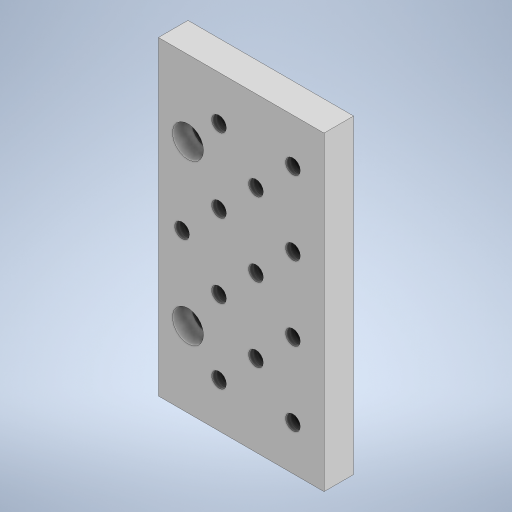
# Autodesk Inventor part: Kinetix_Adapter_V1
Saved by Autodesk Inventor 2023 (Build 270158000, 158)
## iProperties
Created: 2023-07-07
Part Number: Kinetix_Adapter_V1
Material: Generic
Document SubType Name: Modeling
Designer: B0067-WS-2
Density: 1 g/cm^3
Appearance: Default
Author: B0067-WS-2
Autodesk Inventor part; units mm, degrees
ref_plane "YZ Plane" through (0, 0, 0) normal (1, 0, 0) x (0, 1, 0)
ref_plane "XZ Plane" through (0, 0, 0) normal (0, 1, 0) x (-1, 0, 0)
ref_plane "XY Plane" through (0, 0, 0) normal (0, 0, 1) x (1, 0, 0)
sketch "Sketch1" plane through (0, 0, 0) normal (0, 0, 1) x (1, 0, 0)
  line L0 (-19.2, 0) -> (59.2, 0) construction
  line L1 (0, -73.5) -> (0, 73.5) construction
  line L2 (-8, 52.5) -> (48, 52.5)
  line L3 (48, 52.5) -> (48, -52.5)
  line L4 (48, -52.5) -> (-8, -52.5)
  line L5 (-8, -52.5) -> (-8, 52.5)
  point P0 (0, 0)
  dimension "d0" = 105
  dimension "d1" = 56
  dimension "d2" = 8
  constraints: 8 end point, 2 parallel, 1 horizontal, 1 perpendicular, 1 other
  measures "d0" distance between parallel lines of L4 L2
  measures "d1" distance of L2.start L2.end
  measures "d2" distance between parallel lines of L5 L1
extrude "Extrusion1" add sketch "Sketch1" along normal blind 10
sketch "Sketch2" plane through (0, 0, 10) normal (0, 0, 1) x (1, 0, 0)
  line L0 (-22, 0) -> (62, 0) construction
  line L1 (0, 73.5) -> (0, -73.5) construction
  line L2 (-8, -52.5) -> (48, -52.5) construction
  line L3 (48, -52.5) -> (48, 52.5) construction
  line L4 (48, 52.5) -> (-8, 52.5) construction
  line L5 (-8, 52.5) -> (-8, -52.5) construction
  point P0 (0, 0)
  point P1 (2, 27)
  point P2 (2, -27)
  dimension "d5" = 54
  dimension "d6" = 10
  constraints: 1 symmetric about line
  measures "d5" distance of point (2, -27) point (2, 27)
  measures "d6" distance from line of L5 point (2, 27)
hole "Hole1" at (2, 27, 10) at (2, -27, 10) direction (0, 0, -1) diameter 6.5 end through all counterbore diameter 10.5 counterbore depth 6.5
sketch "Sketch3" plane through (0, 0, 10) normal (0, 0, 1) x (1, 0, 0)
  circle A0 centre (2, 27) radius 5.25 construction
  circle A1 centre (2, -27) radius 5.25 construction
  line L0 (-8, -52.5) -> (48, -52.5) construction
  line L1 (48, -52.5) -> (48, 52.5) construction
  line L2 (48, 52.5) -> (-8, 52.5) construction
  line L3 (-8, 52.5) -> (-8, -52.5) construction
  line L4 (-19.2, 0) -> (59.2, 0) construction
  line L5 (48, 52.5) -> (-8, 52.5) construction
  line L6 (25, 52.5) -> (25, -52.5) construction
  line L7 (-8, -52.5) -> (48, -52.5) construction
  line L8 (12.5, 52.5) -> (12.5, -52.5) construction
  line L9 (37.5, 52.5) -> (37.5, -52.5) construction
  point P0 (0, 0)
  point P1 (0, 0)
  point P2 (25, 0)
  point P3 (25, 25)
  point P4 (25, -25)
  point P5 (12.5, -12.5)
  point P6 (12.5, -37.5)
  point P7 (12.5, 12.5)
  point P8 (12.5, 37.5)
  point P9 (12.5, 0)
  point P10 (37.5, 12.5)
  point P11 (37.5, -12.5)
  point P12 (37.5, -37.5)
  point P13 (37.5, 37.5)
  dimension "d14" = 25
  dimension "d15" = 25
  dimension "d16" = 25
  dimension "d17" = 12.5
  dimension "d18" = 12.5
  dimension "d19" = 25
  dimension "d20" = 12.5
  dimension "d21" = 25
  dimension "d29" = 12.5
  dimension "d30" = 25
  dimension "d31" = 12.5
  dimension "d32" = 12.5
  dimension "d33" = 25
  constraints: 16 point on line, 6 end point, 3 perpendicular, 2 midpoint, 1 coincident
  measures "d14" distance from line of point (0, 0) L6
  measures "d15" distance of point (25, 0) point (25, 25)
  measures "d16" distance of point (25, -25) point (25, 0)
  measures "d17" distance from line of point (0, 0) L8
  measures "d18" distance of point (12.5, 0) point (12.5, -12.5)
  measures "d19" distance of point (12.5, -37.5) point (12.5, -12.5)
  measures "d20" distance of point (12.5, 12.5) point (12.5, 0)
  measures "d21" distance of point (12.5, 37.5) point (12.5, 12.5)
  measures "d29" distance between parallel lines of L6 L9
  measures "d30" distance of point (37.5, 12.5) point (37.5, 37.5)
  measures "d31" distance from line of L4 point (37.5, 12.5)
  measures "d32" distance from line of L4 point (37.5, -12.5)
  measures "d33" distance of point (37.5, -37.5) point (37.5, -12.5)
hole "Hole2" at (0, 0, 10) at (25, 0, 10) at (25, 25, 10) at (25, -25, 10) at (12.5, -12.5, 10) at (12.5, -37.5, 10) at (12.5, 12.5, 10) at (12.5, 37.5, 10) at (37.5, 37.5, 10) at (37.5, 12.5, 10) at (37.5, -12.5, 10) at (37.5, -37.5, 10) direction (0, 0, -1) diameter 4.9784 end through all thread size "1/4-20 UNC" class "2B" standard "ANSI Unified Screw Threads"
body "Solid1"
